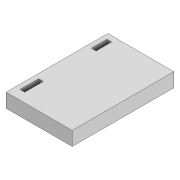
# Autodesk Inventor part: 底版
Saved by Autodesk Inventor 2021 (Build 250183000, 183)
## iProperties
Created: 2024-05-15
Part Number: 底版
Material: 常规
Document SubType Name: Modeling
Designer: teacher
Density: 1 g/cm^3
Appearance: 默认
Author: teacher
Autodesk Inventor part; units mm, degrees
ref_plane "YZ Plane" through (0, 0, 0) normal (1, 0, 0) x (0, 1, 0)
ref_plane "XZ Plane" through (0, 0, 0) normal (0, 1, 0) x (-1, 0, 0)
ref_plane "XY Plane" through (0, 0, 0) normal (0, 0, 1) x (1, 0, 0)
sketch "草图1" plane through (0, 0, 0) normal (0, 1, 0) x (-1, 0, 0)
  line L0 (0, 0) -> (14.2174, 0)
  line L1 (14.2174, 0) -> (14.2174, -21.8696)
  line L2 (14.2174, -21.8696) -> (0, -21.8696)
  line L3 (0, -21.8696) -> (0, 0)
  line L4 (13.2174, -2) -> (12.2174, -2)
  line L5 (12.2174, -2) -> (12.2174, -6)
  line L6 (12.2174, -6) -> (13.2174, -6)
  line L7 (13.2174, -6) -> (13.2174, -2)
  line L8 (13.2174, -17.3478) -> (12.2174, -17.3478)
  line L9 (12.2174, -17.3478) -> (12.2174, -20.6957)
  line L10 (12.2174, -20.6957) -> (13.2174, -20.6957)
  line L11 (13.2174, -20.6957) -> (13.2174, -17.3478)
  dimension "d0" = 4
  dimension "d1" = 1
  dimension "d2" = 1
  dimension "d3" = 2
  constraints: 24 end point, 6 parallel, 3 horizontal, 3 perpendicular, 2 point on line
  measures "d0" distance of L4.end L5.end
  measures "d1" distance of L4.start L4.end
  measures "d2" distance between parallel lines of L7 L1
  measures "d3" distance between parallel lines of L0 L4
extrude "拉伸1" add sketch "草图1" along normal blind 3
